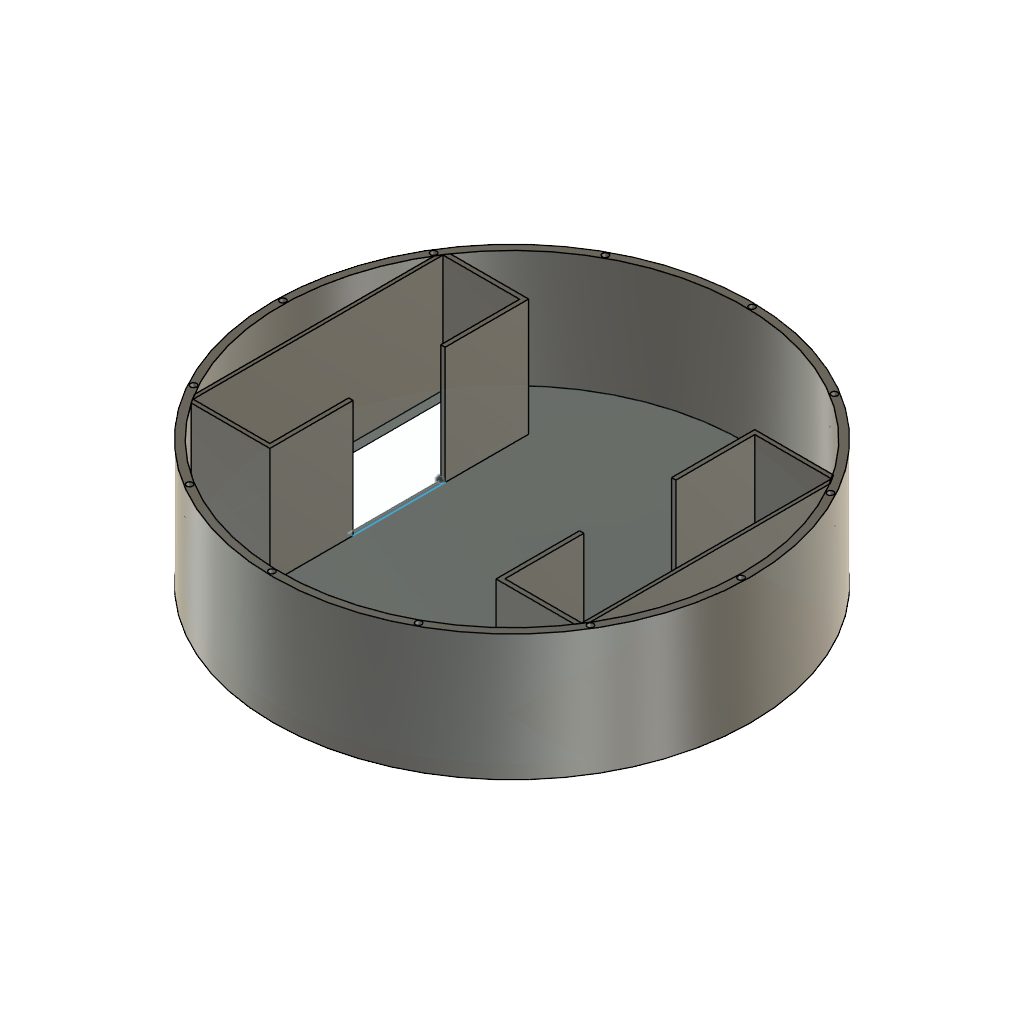
Alfred2.1 (Autodesk Fusion 360 design; units mm, degrees)
part number: 2026-10-07-13-04-34-240
Autodesk Fusion 360 part; units mm, degrees
sketch "Sketch1" plane through (0, 0, 0) normal (0, 0, 1) x (1, 0, 0)
  circle A0 centre (0, 0) radius 76.2
  dimension "d1" = 152.4
  constraint coincident A0.centre origin
  measures "d1" diameter of A0
extrude "Extrude1" add sketch "Sketch1" along normal blind 38.1 thin wall 1 inside makes body 1
sketch "Sketch2" plane through (0, 0, 38.1) normal (0, 0, 1) x (-1, 0, 0)
  circle A0 centre (0, 0) radius 75.2
  circle A1 centre (0, 0) radius 76.2
  circle A2 centre (0, 0) radius 76.2
  constraint concentric A0 A2
extrude "Extrude2" add sketch "Sketch2" along normal blind 3 contours A0 | A1 A2 bodies 1
move_body "Move1" bodies 1 to x (-1, 0, 0) y (0, 1, 0) z (0, 0, -1) at (38.1706, 0, 82.2)
sketch "Sketch3" plane through (0, 0, 44.1) normal (0, 0, 1) x (-1, 0, 0)
  circle A0 centre (-38.1706, 0) radius 75.2
  line L0 (24.9369, 0) -> (24.9369, -40.64)
  line L1 (24.9369, -40.64) -> (0, -40.64)
  line L2 (0, -40.64) -> (0, 0)
  line L3 (24.9369, 40.64) -> (0, 40.64)
  line L4 (0, 40.64) -> (0, 0)
  line L5 (24.9369, 0) -> (24.9369, 40.64)
  line L6 (-101.4433, 40.64) -> (-76.5063, 40.64)
  line L7 (-76.5063, 40.64) -> (-76.5063, -40.64)
  line L8 (-76.5063, -40.64) -> (-101.4433, -40.64)
  line L9 (-101.4433, -40.64) -> (-101.4433, 40.64)
  spline S0 degree 5 poles (24.9369, -40.64) (19.9495, -40.64) (14.9622, -40.64) (9.9748, -40.64) (4.9874, -40.64) (0, -40.64) knots 0 0 0 0 0 0 0.197317 0.197317 0.197317 0.197317 0.197317 0.197317
  line L10 (2.5436, -40.64) -> (-2.5436, -40.64)
  spline S1 degree 5 poles (-76.5063, -40.64) (-81.4937, -40.64) (-86.4811, -40.64) (-91.4685, -40.64) (-96.4559, -40.64) (-101.4433, -40.64) knots 0.802683 0.802683 0.802683 0.802683 0.802683 0.802683 1 1 1 1 1 1
  line L11 (-73.9627, -40.64) -> (-79.0498, -40.64)
  spline S2 degree 5 poles (24.9369, 40.64) (19.9495, 40.64) (14.9622, 40.64) (9.9748, 40.64) (4.9874, 40.64) (0, 40.64) knots 0 0 0 0 0 0 0.197317 0.197317 0.197317 0.197317 0.197317 0.197317
  line L12 (2.5436, 40.64) -> (-2.5436, 40.64)
  spline S3 degree 5 poles (-76.5063, 40.64) (-81.4937, 40.64) (-86.4811, 40.64) (-91.4685, 40.64) (-96.4559, 40.64) (-101.4433, 40.64) knots 0.802683 0.802683 0.802683 0.802683 0.802683 0.802683 1 1 1 1 1 1
  line L13 (-73.9627, 40.64) -> (-79.0498, 40.64)
  dimension "d7" = 40.64
  dimension "d8" = 24.937
  constraint vertical L0
  constraint horizontal L1
  constraint vertical L2
  constraint coincident L2.end L4.end
  constraint coincident A0 L8.end
  constraint coincident A0 L6.start
  constraint horizontal L6
  constraint vertical L7
  constraint horizontal L8
  constraint vertical L9
  constraint midpoint L1.end L10
  constraint midpoint L7.end L11
  constraint midpoint L3.end L12
  constraint midpoint L6.end L13
  measures "d7" distance of L2.end L1.end
  measures "d8" distance of L6.start L6.end
extrude "Extrude3" cut sketch "Sketch3" against normal blind 45 contours L6 L7 L8 L9 S1 L11 S3 L13 | L0 L1 L2 L3 L4 L5 S0 L10 S2 L12 bodies 1
sketch "Sketch4" plane through (0, 0, 82.2) normal (0, 0, 1) x (-1, 0, 0)
  circle A0 centre (-38.1706, 0) radius 75.2
  circle A1 centre (-38.1706, 0) radius 76.2
  circle A2 centre (-38.1706, 0) radius 76.2
  constraint concentric A0 A2
extrude "Extrude4" add sketch "Sketch4" along normal blind 3 separate body contours A0 | A1 A2 makes body 2
sketch "Sketch5" plane through (0, 0, 41.1) normal (0, 0, -1) x (1, 0, 0)
  line L0 (76.5063, 40.64) -> (101.4433, 40.64)
  line L1 (101.4433, 40.64) -> (101.4433, -40.64)
  line L2 (101.4433, -40.64) -> (76.5063, -40.64)
  line L3 (76.5063, -40.64) -> (76.5063, 40.64)
  line L4 (-24.9369, 40.64) -> (0, 40.64)
  line L5 (0, 40.64) -> (0, -40.64)
  line L6 (0, -40.64) -> (-24.9369, -40.64)
  line L7 (-24.9369, -40.64) -> (-24.9369, 40.64)
  circle A0 centre (38.1706, 0) radius 76.2
  circle A1 centre (38.1706, 0) radius 77.7
  dimension "d13" = 155.4
  constraint concentric A0 A1
  measures "d13" diameter of A1
extrude "Extrude5" add sketch "Sketch5" against normal blind 41.1 contours A1 bodies 1
sketch "Sketch6" plane through (0, 0, 85.2) normal (0, 0, 1) x (-1, 0, 0)
  circle A0 centre (-38.1706, 0) radius 76.2
  circle A1 centre (-38.1706, 0) radius 77.6706
  constraint concentric A0 A1
extrude "Extrude6" add sketch "Sketch6" against normal up to surface (3 mm away) bodies 2
sketch "Sketch7" plane through (0, 0, 85.2) normal (0, 0, 1) x (-1, 0, 0)
  circle A0 centre (-38.1706, 0) radius 77.6706
  circle A1 centre (-39.9559, -76.3404) radius 1
  circle A2 centre (-1.5465, -67.0054) radius 1
  circle A3 centre (27.0495, -39.7163) radius 1
  circle A4 centre (38.1698, -1.7853) radius 1
  circle A5 centre (28.8347, 36.6241) radius 1
  circle A6 centre (1.5457, 65.2201) radius 1
  circle A7 centre (-36.3853, 76.3404) radius 1
  circle A8 centre (-74.7947, 67.0054) radius 1
  circle A9 centre (-103.3907, 39.7163) radius 1
  circle A10 centre (-114.511, 1.7853) radius 1
  circle A11 centre (-105.176, -36.6241) radius 1
  circle A12 centre (-77.8869, -65.2201) radius 1
  dimension "d18" = 2
  dimension "d20" = 360
  measures "d18" diameter of A1
extrude "Extrude7" cut sketch "Sketch7" against normal blind 12 contours A1 | A2 | A3 | A4 | A5 | A6 | A7 | A8 | A9 | A10 | A11 | A12 bodies 1 2
sketch "Sketch8" plane through (0, 0, 41.1) normal (0, 0, -1) x (1, 0, 0)
  circle A0 centre (38.1706, 0) radius 77.7
  line L0 (76.5063, 40.64) -> (101.4433, 40.64)
  line L1 (101.4433, 40.64) -> (101.4433, -40.64)
  line L2 (101.4433, -40.64) -> (76.5063, -40.64)
  line L3 (76.5063, -40.64) -> (76.5063, 40.64)
  line L4 (-24.9369, 40.64) -> (0, 40.64)
  line L5 (0, 40.64) -> (0, -40.64)
  line L6 (0, -40.64) -> (-24.9369, -40.64)
  line L7 (-24.9369, -40.64) -> (-24.9369, 40.64)
  line L8 (-24.9369, 40.64) -> (0, 40.64)
  line L9 (0, 40.64) -> (0, -40.64)
  line L10 (0, -40.64) -> (-24.9369, -40.64)
  line L11 (-24.9369, -40.64) -> (-24.9369, 40.64)
  line L12 (76.5063, 40.64) -> (101.4433, 40.64)
  line L13 (101.4433, 40.64) -> (101.4433, -40.64)
  line L14 (101.4433, -40.64) -> (76.5063, -40.64)
  line L15 (76.5063, -40.64) -> (76.5063, 40.64)
  constraint horizontal L8
  constraint vertical L9
  constraint horizontal L10
  constraint vertical L11
  constraint coincident L5.end L6.start
  constraint coincident L4.start L7.end
  constraint horizontal L12
  constraint vertical L13
  constraint horizontal L14
  constraint vertical L15
  constraint coincident L1.end L2.start
  constraint coincident L0.start L3.end
extrude "Extrude8" cut sketch "Sketch8" against normal blind 60 contours L0 L1 L2 L3 L12 L13 L14 L15 | L4 L5 L6 L7 L8 L9 L10 L11 bodies 2
sketch "Sketch9" plane through (0, 0, 44.1) normal (0, 0, 1) x (-1, 0, 0)
  line L0 (-76.5063, -40.64) -> (-101.4433, -40.64)
  arc A0 (-101.4433, -40.64) -> (-101.4433, 40.64) centre (-38.1706, 0) ccw
  line L1 (-101.4433, 40.64) -> (-76.5063, 40.64)
  line L2 (-76.5063, 40.64) -> (-76.5063, -40.64)
  line L3 (0, 40.64) -> (24.9369, 40.64)
  line L4 (24.9369, 40.64) -> (24.9369, -40.64)
  line L5 (24.9369, -40.64) -> (0, -40.64)
  line L6 (0, -40.64) -> (0, 40.64)
  line L7 (0, -40.64) -> (26.0827, -40.64)
  line L8 (26.0827, -40.64) -> (26.0827, -42.1627)
  line L9 (26.0827, -42.1627) -> (0, -42.1627)
  line L10 (0, -42.1627) -> (0, -40.64)
  line L11 (24.9369, 40.64) -> (0, 40.64)
  line L12 (0, 40.64) -> (0, 42.0226)
  line L13 (0, 42.0226) -> (24.9369, 42.0226)
  line L14 (24.9369, 42.0226) -> (24.9369, 40.64)
  line L15 (26.0827, -41.4013) -> (24.9369, -41.4013)
  line L16 (24.9369, -41.4013) -> (24.9369, 42.0226)
  line L17 (24.9369, 42.0226) -> (26.0827, 42.0226)
  line L18 (26.0827, 42.0226) -> (26.0827, -41.4013)
  line L19 (0, -42.1627) -> (-1.4084, -42.1627)
  line L20 (-1.4084, -42.1627) -> (-1.4084, 42.0226)
  line L21 (-1.4084, 42.0226) -> (0, 42.0226)
  line L22 (0, 42.0226) -> (0, -42.1627)
  line L23 (0, -15) -> (-1.4084, -15)
  line L24 (-1.4084, -15) -> (-1.4084, 14.9615)
  line L25 (-1.4084, 14.9615) -> (0, 14.9615)
  line L26 (0, 14.9615) -> (0, -15)
  constraint horizontal L7
  constraint vertical L8
  constraint horizontal L9
  constraint vertical L10
  constraint coincident L5.end L6.start
  constraint horizontal L11
  constraint vertical L12
  constraint horizontal L13
  constraint vertical L14
  constraint coincident L3.end L4.start
  constraint horizontal L15
  constraint vertical L16
  constraint horizontal L17
  constraint vertical L18
  constraint midpoint L8 L15.start
  constraint horizontal L19
  constraint vertical L20
  constraint horizontal L21
  constraint vertical L22
  constraint horizontal L23
  constraint vertical L24
  constraint horizontal L25
  constraint vertical L26
  constraint coincident L20 L24.end
  constraint coincident L6 L23.start
extrude "Extrude9" add sketch "Sketch9" along normal up to surface (38.1 mm away) separate body contours A0 L5 L7 L9 L10 L16 L22 | L6 L10 L19 L20 L22 L23 | A0 L3 L11 L12 L13 L14 L16 L22 | A0 L4 L7 L14 L16 L18 | L6 L12 L20 L21 L22 L25 makes body 3
sketch "Sketch10" plane through (0, 0, 44.1) normal (0, 0, 1) x (-1, 0, 0)
  line L0 (-76.5063, -40.64) -> (-101.4433, -40.64)
  arc A0 (-101.4433, -40.64) -> (-101.4433, 40.64) centre (-38.1706, 0) ccw
  line L1 (-101.4433, 40.64) -> (-76.5063, 40.64)
  line L2 (-76.5063, 40.64) -> (-76.5063, -40.64)
  line L3 (0, 40.64) -> (24.9369, 40.64)
  line L4 (24.9369, 40.64) -> (24.9369, -40.64)
  line L5 (24.9369, -40.64) -> (0, -40.64)
  line L6 (0, -40.64) -> (0, 40.64)
  line L7 (0, -15.0056) -> (-1.4, -15.0056)
  line L8 (-1.4, -15.0056) -> (-1.4, 15)
  line L9 (-1.4, 15) -> (0, 15)
  line L10 (0, 15) -> (0, -15.0056)
  constraint horizontal L7
  constraint vertical L8
  constraint horizontal L9
  constraint vertical L10
  constraint coincident L6 L7.start
pattern_linear "R-Pattern1" count 2 spacing 155 along (1, 0, 0) of bodies 3 makes body 4
move_body "Move2" bodies 4 to x (-1, 0, 0) y (0, -1, 0) z (0, 0, 1) at (231.3966, 0.1478, 0)
hidden bodies 2
named bodies: "Lid"
